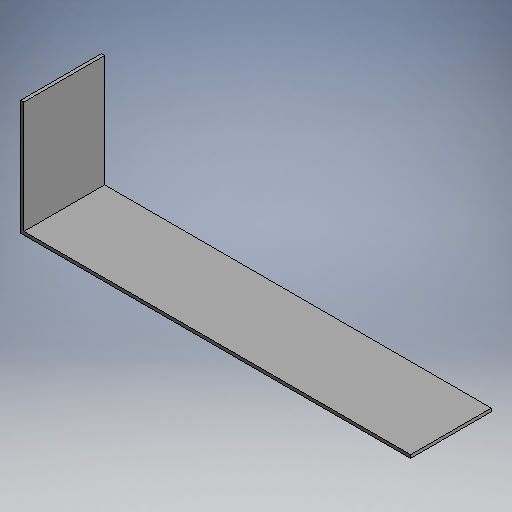
# Autodesk Inventor part: Drywall_Corner_Walls
Saved by Autodesk Inventor 2026.2 (Build 302298000, 298)
## iProperties
Part Number: Drywall_Corner_Walls
Material: Generic
Document SubType Name: Modeling
Designer: Jacob
Appearance: Default
Author: Jacob
Autodesk Inventor part; units mm, degrees
ref_plane "YZ Plane" through (0, 0, 0) normal (1, 0, 0) x (0, 1, 0)
ref_plane "XZ Plane" through (0, 0, 0) normal (0, 1, 0) x (-1, 0, 0)
ref_plane "XY Plane" through (0, 0, 0) normal (0, 0, 1) x (1, 0, 0)
sketch "Sketch1" plane through (0, 0, 0) normal (0, 0, 1) x (1, 0, 0)
  line L0 (-120, -120) -> (14376.4, -120)
  line L1 (14376.4, -120) -> (14376.4, 0)
  line L2 (14376.4, 0) -> (-120, 0)
  line L3 (-120, 0) -> (-120, -120)
  constraints: 8 end point, 2 parallel, 1 horizontal, 1 perpendicular
extrude "Extrusion1" add sketch "Sketch1" along normal blind 3000
sketch "Sketch2" plane through (0, 0, 0) normal (0, 0, 1) x (1, 0, 0)
  line L0 (-120, 0) -> (0, 0)
  line L1 (0, 0) -> (0, 4165.6)
  line L2 (0, 4165.6) -> (-120, 4165.6)
  line L3 (-120, 4165.6) -> (-120, 0)
  constraints: 8 end point, 2 parallel, 1 horizontal, 1 perpendicular
extrude "Extrusion2" add sketch "Sketch2" along normal blind 3000
body "Solid1"
